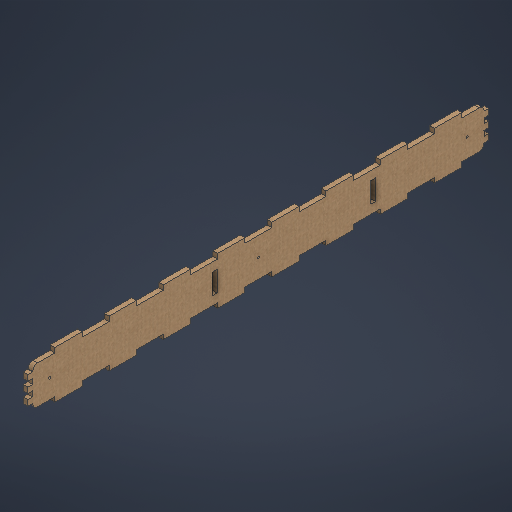
# Autodesk Inventor part: BaseBoxWidthFace
Saved by Autodesk Inventor 2027.1 (Build 311270010, 270A)
## iProperties
Created: 2026-10-13
Part Number: BaseBoxWidthFace
Material: MDF Medium Density Fiberboard
Document SubType Name: Modeling
Designer: SDS Scholar
Density: 0.8 g/cm^3
Appearance: Cardboard - Corrugated
Mass: 255.584 g
Surface Area: 1013.88 cm^2
Volume: 319.48 cm^3
Author: SDS Scholar
Autodesk Inventor part; units mm, degrees
ref_plane "YZ Plane" through (0, 0, 0) normal (1, 0, 0) x (0, 1, 0)
ref_plane "XZ Plane" through (0, 0, 0) normal (0, 1, 0) x (-1, 0, 0)
ref_plane "XY Plane" through (0, 0, 0) normal (0, 0, 1) x (1, 0, 0)
sketch "Sketch1" plane through (0, 0, 0) normal (1, 0, 0) x (0, 1, 0)
  line L0 (35, 340) -> (-35, 340)
  line L1 (-35, 340) -> (-35, -340)
  line L2 (-35, -340) -> (35, -340)
  line L3 (35, -340) -> (35, 340)
  point P0 (0, 0)
  point P1 (0, -340)
  point P2 (35, 0)
  dimension "d0" = 680
  dimension "d1" = 70
  constraints: 8 end point, 2 midpoint, 2 parallel, 1 horizontal, 1 horizontal alignment, 1 perpendicular, 1 vertical alignment
  measures "d0" distance of L2.end L0.start
  measures "d1" distance of L0.start L0.end
extrude "Extrusion1" add sketch "Sketch1" along normal blind 7
sketch "Sketch3" plane through (7, 0, 0) normal (1, 0, 0) x (0, 0, -1)
  line L0 (-340, -35) -> (340, -35) projected
  line L1 (340, -35) -> (340, 35) projected
  line L2 (340, 35) -> (-340, 35) projected
  line L3 (-340, 35) -> (-340, -35) projected
  line L4 (-333, 28) -> (333, 28)
  line L5 (333, 28) -> (333, -28)
  line L6 (333, -28) -> (-333, -28)
  line L7 (-333, -28) -> (-333, 28)
  line L8 (-340, 35) -> (-300.225, 35)
  line L9 (-300.225, 35) -> (-300.225, 28)
  line L10 (-300.225, 28) -> (-340, 28)
  line L11 (-340, 28) -> (-340, 35)
  line L12 (-300.225, 35) -> (-259.775, 35)
  line L13 (-259.775, 35) -> (-259.775, 28)
  line L14 (-259.775, 28) -> (-300.225, 28)
  line L15 (-300.225, 28) -> (-300.225, 35)
  line L16 (-179.775, 35) -> (-179.775, 28)
  line L17 (-220.225, 35) -> (-220.225, 28)
  line L18 (-99.775, 35) -> (-99.775, 28)
  line L19 (-140.225, 35) -> (-140.225, 28)
  line L20 (-19.775, 35) -> (-19.775, 28)
  line L21 (-60.225, 35) -> (-60.225, 28)
  line L22 (60.225, 35) -> (60.225, 28)
  line L23 (19.775, 35) -> (19.775, 28)
  line L24 (140.225, 35) -> (140.225, 28)
  line L25 (99.775, 35) -> (99.775, 28)
  line L26 (220.225, 35) -> (220.225, 28)
  line L27 (179.775, 35) -> (179.775, 28)
  line L28 (300.225, 35) -> (300.225, 28)
  line L29 (259.775, 35) -> (259.775, 28)
  line L30 (-340, 0) -> (340, 0) construction
  line L31 (340, 35) -> (-340, 35) projected
  line L32 (0, 35) -> (0, -35) construction
  line L33 (-300.225, -35) -> (-300.225, -28)
  line L34 (-259.775, -35) -> (-259.775, -28)
  line L35 (-179.775, -35) -> (-179.775, -28)
  line L36 (-220.225, -35) -> (-220.225, -28)
  line L37 (-99.775, -35) -> (-99.775, -28)
  line L38 (-140.225, -35) -> (-140.225, -28)
  line L39 (-19.775, -35) -> (-19.775, -28)
  line L40 (-60.225, -35) -> (-60.225, -28)
  line L41 (60.225, -35) -> (60.225, -28)
  line L42 (19.775, -35) -> (19.775, -28)
  line L43 (140.225, -35) -> (140.225, -28)
  line L44 (99.775, -35) -> (99.775, -28)
  line L45 (220.225, -35) -> (220.225, -28)
  line L46 (179.775, -35) -> (179.775, -28)
  line L47 (300.225, -35) -> (300.225, -28)
  line L48 (259.775, -35) -> (259.775, -28)
  line L49 (0, -35) -> (0, 35) construction
  line L50 (-340, 28) -> (-333, 28)
  line L51 (-333, 28) -> (-333, 20.225)
  line L52 (-333, 20.225) -> (-340, 20.225)
  line L53 (-340, 20.225) -> (-340, 28)
  line L54 (-340, 20.225) -> (-333, 20.225)
  line L55 (-333, 20.225) -> (-333, 11.775)
  line L56 (-333, 11.775) -> (-340, 11.775)
  line L57 (-340, 11.775) -> (-340, 20.225)
  line L58 (-333, -28) -> (-340, -28)
  line L59 (-333, -4.225) -> (-340, -4.225)
  line L60 (-333, 4.225) -> (-340, 4.225)
  line L61 (-333, -20.225) -> (-340, -20.225)
  line L62 (-333, -11.775) -> (-340, -11.775)
  line L63 (300.225, 28) -> (340, 28)
  line L64 (333, 20.225) -> (340, 20.225)
  line L65 (333, 11.775) -> (340, 11.775)
  line L66 (333, -28) -> (340, -28)
  line L67 (333, -4.225) -> (340, -4.225)
  line L68 (333, 4.225) -> (340, 4.225)
  line L69 (333, -20.225) -> (340, -20.225)
  line L70 (333, -11.775) -> (340, -11.775)
  line L71 (-333, 28) -> (-333, 35)
  line L72 (-333, -28) -> (-333, -35)
  line L73 (333, 28) -> (333, 35)
  line L74 (333, -28) -> (333, -35)
  point P0 (0, 0)
  point P1 (333, -11.775)
  point P2 (333, -20.225)
  point P3 (333, -4.225)
  point P4 (333, 4.225)
  point P5 (333, 11.775)
  point P6 (333, 20.225)
  point P7 (-333, 4.225)
  point P8 (-333, -4.225)
  point P9 (-333, -11.775)
  point P10 (-333, -20.225)
  point P11 (-300.225, -35)
  point P12 (-300.225, -28)
  point P13 (-220.225, -35)
  point P14 (-220.225, -28)
  point P15 (-259.775, -28)
  point P16 (-259.775, -35)
  point P17 (-140.225, -35)
  point P18 (-140.225, -28)
  point P19 (-179.775, -28)
  point P20 (-179.775, -35)
  point P21 (-60.225, -35)
  point P22 (-60.225, -28)
  point P23 (-99.775, -28)
  point P24 (-99.775, -35)
  point P25 (19.775, -35)
  point P26 (19.775, -28)
  point P27 (-19.775, -28)
  point P28 (-19.775, -35)
  point P29 (99.775, -35)
  point P30 (99.775, -28)
  point P31 (60.225, -28)
  point P32 (60.225, -35)
  point P33 (179.775, -35)
  point P34 (179.775, -28)
  point P35 (140.225, -28)
  point P36 (140.225, -35)
  point P37 (220.225, -28)
  point P38 (300.225, -35)
  point P39 (300.225, 35)
  point P40 (300.225, 28)
  point P41 (259.775, 28)
  point P42 (259.775, 35)
  point P43 (220.225, 35)
  point P44 (220.225, 28)
  point P45 (179.775, 28)
  point P46 (179.775, 35)
  point P47 (140.225, 35)
  point P48 (140.225, 28)
  point P49 (99.775, 28)
  point P50 (99.775, 35)
  point P51 (60.225, 35)
  point P52 (60.225, 28)
  point P53 (19.775, 28)
  point P54 (19.775, 35)
  point P55 (-19.775, 35)
  point P56 (-19.775, 28)
  point P57 (-60.225, 28)
  point P58 (-60.225, 35)
  point P59 (-99.775, 35)
  point P60 (-99.775, 28)
  point P61 (-140.225, 28)
  point P62 (-140.225, 35)
  point P63 (-179.775, 35)
  point P64 (-179.775, 28)
  point P65 (-220.225, 28)
  point P66 (-220.225, 35)
  point P67 (-333, 28)
  point P68 (333, 28)
  point P69 (333, 35)
  point P70 (333, 28)
  point P71 (-333, 28)
  point P72 (-333, 35)
  dimension "d9" = 7
  dimension "d10" = 39.775
  dimension "d11" = 40.45
  dimension "d14" = 80
  dimension "d20" = 7.775
  dimension "d21" = 8.45
  dimension "d24" = 16
  constraints: 138 end point, 49 symmetric about line, 28 horizontal alignment, 23 parallel, 6 perpendicular, 5 point on line, 4 horizontal, 2 midpoint, 2 vertical, 28 other
  measures "d10" distance between parallel lines of L3 L9
  measures "d11" distance between parallel lines of L9 L13
  measures "d14" distance of L12.end L16.start
  measures "d20" distance between parallel lines of L10 L52
  measures "d21" distance between parallel lines of L54 L56
  measures "d24" distance of L55.end L59.start
extrude "Extrusion3" cut sketch "Sketch3" against normal through all contours L3 L58 L72 L0 | L72 L6 L33 L0 | L3 L61 L7 L58 | L34 L6 L36 L0 | L3 L59 L7 L62 | L35 L6 L38 L0 | L3 L56 L7 L60 | L37 L6 L40 L0 | L3 L10 L7 L52 | L3 L2 L71 L10 | L39 L6 L42 L0 | L71 L2 L9 L4 | L41 L6 L44 L0 | L13 L2 L17 L4 | L43 L6 L46 L0 | L16 L2 L19 L4 | L45 L6 L48 L0 | L18 L2 L21 L4 | L47 L6 L74 L0 | L20 L2 L23 L4 | L74 L66 L1 L0 | L5 L69 L1 L66 | L22 L2 L25 L4 | L5 L67 L1 L70 | L24 L2 L27 L4 | L5 L65 L1 L68 | L26 L2 L29 L4 | L5 L63 L1 L64 | L28 L2 L73 L4 | L73 L2 L1 L63
fillet "Fillet3" radius 7 4 edges at (3.5, 28, 333) (3.5, -28, 333) (3.5, 28, -333) (3.5, -28, -333)
sketch "Sketch5" plane through (7, 0, 0) normal (1, 0, 0) x (0, 0, -1)
  line L0 (-340, 0) -> (340, 0) construction
  line L1 (340, -4.225) -> (340, 4.225) projected
  line L2 (-340, 4.225) -> (-340, -4.225) projected
  line L3 (-19.775, 28) -> (19.775, 28) projected
  line L4 (0, 28) -> (0, -28) construction
  line L5 (-19.775, -28) -> (19.775, -28) projected
  line L6 (240, 19.5) -> (240, 16.5) construction
  line L7 (237.1, 19.5) -> (237.1, 16.5)
  line L8 (242.9, 16.5) -> (242.9, 19.5)
  arc A0 (242.9, 19.5) -> (237.1, 19.5) centre (240, 19.5) ccw
  arc A1 (237.1, 16.5) -> (242.9, 16.5) centre (240, 16.5) ccw
  line L9 (259.775, 28) -> (220.225, 28) projected
  line L10 (333, 4.225) -> (333, 11.775) projected
  line L11 (80, 19.5) -> (80, 16.5) construction
  line L12 (77.1, 19.5) -> (77.1, 16.5)
  line L13 (82.9, 16.5) -> (82.9, 19.5)
  arc A2 (82.9, 19.5) -> (77.1, 19.5) centre (80, 19.5) ccw
  arc A3 (77.1, 16.5) -> (82.9, 16.5) centre (80, 16.5) ccw
  line L14 (99.775, 28) -> (60.225, 28) projected
  line L15 (-240, 19.5) -> (-240, 16.5) construction
  line L16 (-237.1, 19.5) -> (-237.1, 16.5)
  line L17 (-242.9, 16.5) -> (-242.9, 19.5)
  arc A4 (-237.1, 19.5) -> (-242.9, 19.5) centre (-240, 19.5) ccw
  arc A5 (-242.9, 16.5) -> (-237.1, 16.5) centre (-240, 16.5) ccw
  line L18 (-80, 19.5) -> (-80, 16.5) construction
  line L19 (-77.1, 19.5) -> (-77.1, 16.5)
  line L20 (-82.9, 16.5) -> (-82.9, 19.5)
  arc A6 (-77.1, 19.5) -> (-82.9, 19.5) centre (-80, 19.5) ccw
  arc A7 (-82.9, 16.5) -> (-77.1, 16.5) centre (-80, 16.5) ccw
  line L21 (240, -19.5) -> (240, -16.5) construction
  line L22 (237.1, -19.5) -> (237.1, -16.5)
  line L23 (242.9, -16.5) -> (242.9, -19.5)
  arc A8 (237.1, -19.5) -> (242.9, -19.5) centre (240, -19.5) ccw
  arc A9 (242.9, -16.5) -> (237.1, -16.5) centre (240, -16.5) ccw
  line L24 (80, -19.5) -> (80, -16.5) construction
  line L25 (77.1, -19.5) -> (77.1, -16.5)
  line L26 (82.9, -16.5) -> (82.9, -19.5)
  arc A10 (77.1, -19.5) -> (82.9, -19.5) centre (80, -19.5) ccw
  arc A11 (82.9, -16.5) -> (77.1, -16.5) centre (80, -16.5) ccw
  line L27 (-77.1, -19.5) -> (-77.1, -16.5)
  line L28 (-80, -19.5) -> (-80, -16.5) construction
  line L29 (-82.9, -16.5) -> (-82.9, -19.5)
  arc A12 (-77.1, -16.5) -> (-82.9, -16.5) centre (-80, -16.5) ccw
  arc A13 (-82.9, -19.5) -> (-77.1, -19.5) centre (-80, -19.5) ccw
  line L30 (-237.1, -19.5) -> (-237.1, -16.5)
  line L31 (-240, -19.5) -> (-240, -16.5) construction
  line L32 (-242.9, -16.5) -> (-242.9, -19.5)
  arc A14 (-237.1, -16.5) -> (-242.9, -16.5) centre (-240, -16.5) ccw
  arc A15 (-242.9, -19.5) -> (-237.1, -19.5) centre (-240, -19.5) ccw
  point P0 (0, 0)
  point P1 (240, 18)
  point P2 (80, 18)
  point P3 (-240, 18)
  point P4 (-80, 18)
  point P5 (240, -18)
  point P6 (80, -18)
  point P7 (-80, -18)
  point P8 (-240, -18)
  dimension "d44" = 3
  dimension "d45" = 5.8
  dimension "d46" = 8.5
  dimension "d48" = 3
  dimension "d49" = 5.8
  dimension "d50" = 8.5
  dimension "d51" = 160
  dimension "d54" = 100
  constraints: 68 end point, 42 symmetric about line, 32 point on circle, 16 centre point, 8 tangent, 7 midpoint, 2 parallel, 2 perpendicular, 1 coincident, 1 horizontal, 1 vertical, 12 other
  measures "d44" distance of L6.start L6.end
  measures "d45" diameter of A1
  measures "d46" distance from line of L9 L6.start
  measures "d48" distance of L11.start L11.end
  measures "d49" diameter of A3
  measures "d50" distance from line of L14 L11.start
  measures "d51" distance between parallel lines of L6 L11
  measures "d54" distance between parallel lines of L1 L6
extrude "Extrusion5" [suppressed]
sketch "Sketch6" plane through (7, 0, 0) normal (1, 0, 0) x (0, 0, -1)
  line L0 (173, 15) -> (166, 15)
  line L1 (166, 15) -> (166, -15)
  line L2 (166, -15) -> (173, -15)
  line L3 (173, -15) -> (173, 15)
  line L4 (340, -4.225) -> (340, 4.225) projected
  line L5 (-68, 15) -> (-61, 15)
  line L6 (-61, 15) -> (-61, -15)
  line L7 (-61, -15) -> (-68, -15)
  line L8 (-68, -15) -> (-68, 15)
  line L9 (-340, 4.225) -> (-340, -4.225) projected
  line L10 (333, -11.775) -> (333, -4.225) projected
  line L11 (-333, -4.225) -> (-333, -11.775) projected
  point P0 (0, 0)
  point P1 (173, 0)
  point P2 (340, 0)
  point P3 (-68, 0)
  point P4 (-340, 0)
  dimension "d55" = 7
  dimension "d56" = 30
  dimension "d58" = 7
  dimension "d59" = 30
  dimension "d63" = 160
  dimension "d64" = 265
  constraints: 16 end point, 4 midpoint, 4 parallel, 2 horizontal, 2 horizontal alignment, 2 perpendicular
  measures "d55" distance of L2.end L1.end
  measures "d56" distance of L1.end L0.end
  measures "d58" distance of L6.end L7.end
  measures "d59" distance of L5.end L6.end
  measures "d63" distance between parallel lines of L10 L3
  measures "d64" distance between parallel lines of L8 L11
extrude "Extrusion6" cut sketch "Sketch6" against normal through all
sketch "Sketch7" plane through (0, 0, 0) normal (-1, 0, 0) x (0, 0, 1)
  circle A0 centre (-308, 0) radius 1.5
  circle A1 centre (0, 0) radius 1.5
  circle A2 centre (308, 0) radius 1.5
  line L0 (-333, 11.775) -> (-333, 4.225) projected
  line L1 (-340, -4.225) -> (-340, 4.225) projected
  line L2 (340, 4.225) -> (340, -4.225) projected
  line L3 (333, 4.225) -> (333, 11.775) projected
  point P0 (-340, 0)
  point P1 (340, 0)
  dimension "d65" = 3
  dimension "d66" = 3
  dimension "d67" = 3
  dimension "d68" = 25
  dimension "d69" = 25
  constraints: 3 centre point, 2 horizontal alignment, 2 midpoint, 1 coincident
  measures "d65" diameter of A0
  measures "d66" diameter of A1
  measures "d67" diameter of A2
  measures "d68" distance from line of L0 A0.centre
  measures "d69" distance from line of L3 A2.centre
extrude "Extrusion7" cut sketch "Sketch7" against normal through all
equation "\"d0\" = BaseTotalWidth"
equation "\"d1\" = BaseHeight"
equation "\"d2\" = BaseWoodThickness"
equation "\"d9\" = BaseWoodThickness"
equation "\"GridProcutClearance\" = 5"
equation "\"GridBorderThickness\" = 5"
equation "\"GridBorderFillets\" = 7"
equation "\"GridTotalSize\" = 65"
equation "\"GridRobotClearance\" = 65"
equation "\"AluminiumExtrusionClearance\" = 35"
equation "\"BaseTotalWidth\" = 680"
equation "\"BaseTotalLength\" = 885"
equation "\"WorkspaceLength\" = 515"
equation "\"WorkspaceHeight\" = 183"
equation "\"AxesBaseFillet\" = 15"
equation "\"Zaxis\" = 197"
equation "\"ProductTotalHeight\" = 45"
equation "\"VerticalStroke\" = 105"
equation "\"BackArea\" = 165"
equation "\"CylinderStroke\" = 75"
equation "\"BaseHeight\" = 70"
equation "\"BoxesWidth\" = 125"
equation "\"BaseWoodThickness\" = 7"
equation "\"kerf\" = 1.5"
equation "\"Kerf\" = 0.3"
equation "\"RxThickness\" = 1.8"
equation "\"support_2\" = 265"
body "Solid1"
